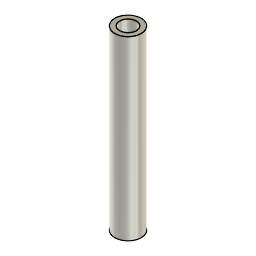
Hexapod (Autodesk Fusion 360 archive; units mm, degrees)
design "Support"
Autodesk Fusion 360 part; units mm, degrees
sketch "Sketch1" plane through (0, 0, 0) normal (0, 0, 1) x (1, 0, 0)
  circle A0 centre (0, 0) radius 3
  circle A1 centre (0, 0) radius 1.9
  dimension "d1" = 6
  dimension "d2" = 3.8
  constraint coincident A0.centre A1.centre
  measures "d1" diameter of A0
  measures "d2" diameter of A1
extrude "Extrude1" add sketch "Sketch1" along normal blind 40

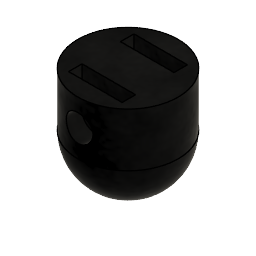
design "Tip"
Autodesk Fusion 360 part; units mm, degrees
sphere "SpherePrimitive1" add diameter 15 placed x (1, 0, 0) y (0, 1, 0) z (0, 0, 1) at (0, 0, 0)
ref_plane "WorkPlane1" through (0, 0, 0) normal (0, 0, 1) x (1, 0, 0)
sketch "Sketch2" plane through (0, 0, 0) normal (0, 0, 1) x (1, 0, 0)
  circle A0 centre (0, 0) radius 7.5
  dimension "d3" = 15
  constraint coincident A0.centre origin
  measures "d3" diameter of A0
extrude "Extrude1" cut sketch "Sketch2" along normal blind 8
extrude "Extrude2" add 1 faces at (1.9158, 2.8099, 0) along direction (0, 0, 1) blind 8
sketch "Sketch3" plane through (0, 0, 8) normal (0, 0, 1) x (-1, 0, 0)
  circle A0 centre (0, 0) radius 7.5
  line L0 (-4, 4.881) -> (4, 4.881)
  line L1 (-4, -4.881) -> (4, -4.881)
  line L2 (-4, -2.881) -> (4, -2.881)
  line L3 (-4, 2.881) -> (4, 2.881)
  line L4 (-4, -4.881) -> (-4, 4.881)
  line L5 (4, 4.881) -> (4, -4.881)
  line L6 (-4, 4.881) -> (-4, 6.3443)
  line L7 (-4, -4.881) -> (-4, -6.3443)
  line L8 (4, 4.881) -> (4, 6.3443)
  line L9 (4, -4.881) -> (4, -6.3443)
  dimension "d8" = 4.881
  dimension "d9" = 4.881
  dimension "d10" = 4
  dimension "d11" = 2
  dimension "d12" = 2
  dimension "d13" = 4
  constraint horizontal L0
  constraint parallel L0 L1
  constraint horizontal L2
  constraint parallel L2 L3
  constraint perpendicular L0 L4
  constraint perpendicular L1 L5
  constraint coincident L4 L2.start
  constraint coincident L4 L3.start
  constraint coincident L5 L3.end
  constraint coincident L5 L2.end
  constraint perpendicular L0 L6
  constraint perpendicular L1 L7
  constraint perpendicular L0 L8
  constraint perpendicular L1 L9
  constraint coincident A0 L6.end
  constraint coincident A0 L8.end
  constraint coincident A0 L7.end
  constraint coincident A0 L9.end
  measures "d8" distance of A0.centre L0
  measures "d9" distance of A0.centre L1
  measures "d10" distance of A0.centre L5
  measures "d11" distance of L1 L2
  measures "d12" distance of L0 L3
  measures "d13" distance of A0.centre L4
extrude "Extrude3" cut sketch "Sketch3" against normal blind 8 contours L0 L3 L4 L5 | L1 L2 L4 L5
sketch "Sketch4" plane through (0, 2.881, 0) normal (0, 1, 0) x (-1, 0, 0)
  line L0 (4, 8) -> (-4, 8)
  line L1 (-4, 8) -> (-4, 0)
  line L2 (-4, 0) -> (4, 0)
  line L3 (4, 0) -> (4, 8)
  circle A0 centre (0, 4) radius 2
  dimension "d16" = 4
  measures "d16" diameter of A0
extrude "Extrude4" cut sketch "Sketch4" along normal blind 5 and the other way blind 10.5 contours A0
